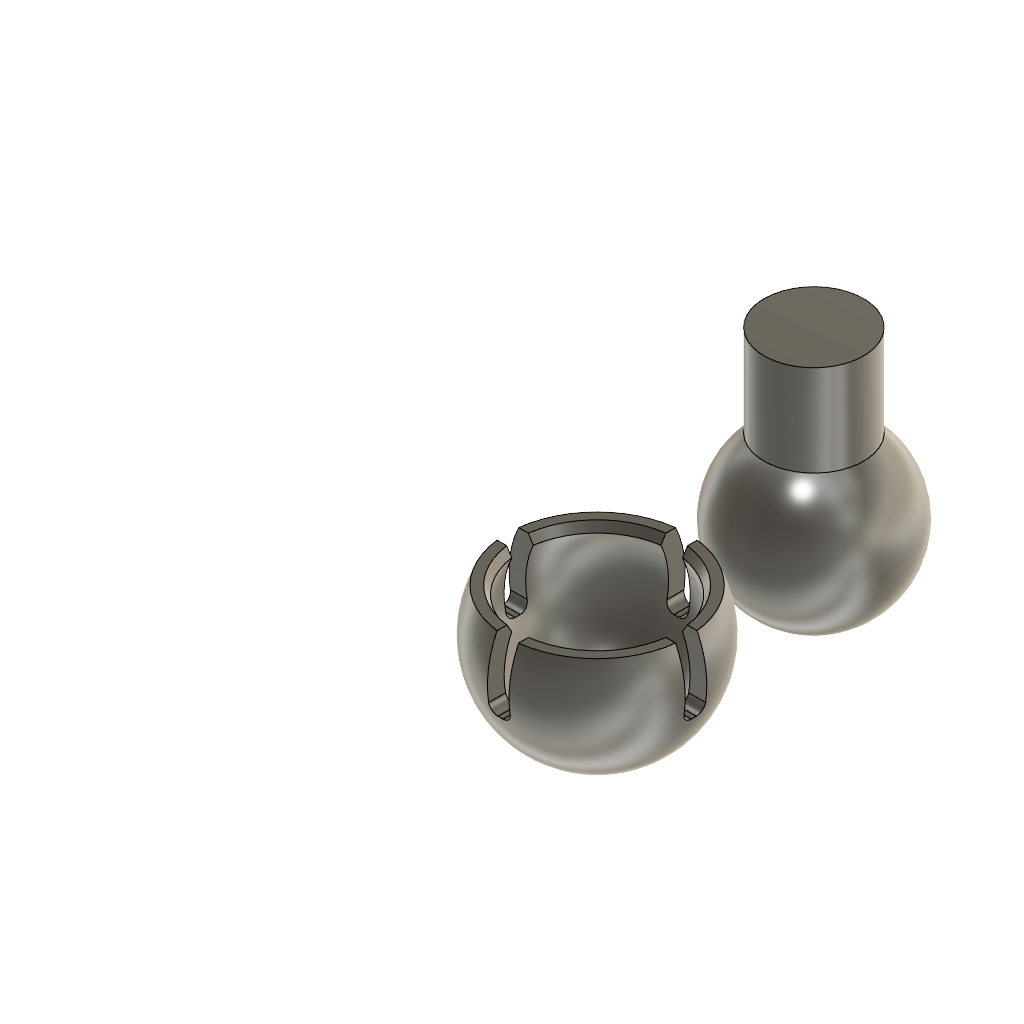
Bal&Socket (Autodesk Fusion 360 design; units mm, degrees)
Autodesk Fusion 360 part; units mm, degrees
sketch "Sketch2" plane through (0, 0, 0) normal (0, 1, 0) x (1, 0, 0)
  line L0 (0, -59.2722) -> (0, 62.6051)
  arc A0 (0, -50) -> (0, 50) centre (0, 0) ccw
  dimension "d5" = 100
  constraint coincident A0.centre origin
  constraint vertical L0
  constraint coincident L0 A0.end
  constraint coincident L0 A0.start
  constraint coincident A0.centre L0
  measures "d5" diameter of A0
revolve "Revolve1" add sketch "Sketch2" angle 360 about axis through (0, 0, 59.2722) along (0, 0, -1) makes body 1
ref_plane "WorkPlane1" through (0, 45, 0) normal (0, 1, 0) x (0, 0, 1)
sketch "Sketch4" plane through (0, 45, 0) normal (0, 1, 0) x (1, 0, 0)
  circle A0 centre (0, 0) radius 50
  circle A1 centre (0, 0) radius 30
  dimension "d9" = 60
  constraint concentric A0 A1
  measures "d9" diameter of A1
extrude "Extrude2" add sketch "Sketch4" along normal blind 55 separate body contours A1 makes body 2
copy_body "CopyPasteBodies1" bodies 1 makes body 3
move_body "Move1" bodies 3 to x (1, 0, 0) y (0, 1, 0) z (0, 0, 1) at (-128.8278, -193.9843, -63.6974)
move_body "Move2" bodies 2 to x (1, 0, 0) y (0, 0, 1) z (0, -1, 0) at (0, 0, 0)
move_face "OffsetFaces1" offset 10 1 faces at (-81.424, -182.1652, -74.3367) on bodies 3
move_body "Move3" bodies 1 2 to x (1, 0, 0) y (0, 1, 0) z (0, 0, 1) at (204.8691, 266.1175, 12.3114)
move_body "Move6" bodies 3 to x (1, 0, 0) y (0, 1, 0) z (0, 0, 1) at (185.6418, 249.1989, 118.0047)
sketch "Sketch6" plane through (0, 0, 0) normal (0, 1, 0) x (1, 0, 0)
ref_plane "WorkPlane2" through (0, 0, 80) normal (0, 0, 1) x (1, 0, 0)
split "Split1" by plane through (0, 0, 80) normal (0, 0, 1) bodies 3 makes body 4 at (101.0581, 47.4131, 94.0768)
copy_body "CopyPasteBodies3" bodies 1 makes body 5
move_body "Move7" bodies 5 to x (1, 0, 0) y (0, 1, 0) z (0, 0, 1) at (-89.9127, -41.461, -15.643)
move_body "Align1" bodies 5 to x (1, 0, 0) y (0, 1, 0) z (0, 0, 1) at (-58.1423, -169.4419, 57.639)
combine "Combine1" operation cut target body 3 tool bodies 5
sketch "Sketch7" plane through (0, 0, 0) normal (0, 1, 0) x (1, 0, 0)
  line L0 (50.3141, -80) -> (63.3141, -80)
  line L1 (63.3141, -80) -> (63.3141, -40)
  line L2 (63.3141, -40) -> (50.3141, -40)
  line L3 (50.3141, -40) -> (50.3141, -80)
  line L4 (56.8141, -80) -> (111.0348, -80)
  line L5 (2.5933, -80) -> (56.8141, -80)
  arc A0 (111.0348, -80) -> (2.5933, -80) centre (56.8141, -54.3074) ccw
  line L6 (-14.997, -80) -> (130.0763, -80)
  dimension "d18" = 40
  dimension "d19" = 13
  constraint horizontal L0
  constraint vertical L1
  constraint horizontal L2
  constraint vertical L3
  constraint parallel L4 L6
  constraint midpoint L0 L4.start
  measures "d18" distance of L0 L2
  measures "d19" distance of L1 L3
extrude "Extrude3" add sketch "Sketch7" along normal blind 130 and the other way blind 70 separate body contours L0 L1 L2 L3 L4 L5 L6 makes body 6
fillet "Fillet1" radius 5 2 edges at (50.3141, 30, 40) (63.3141, 30, 40) on bodies 6
combine "Combine2" operation cut target body 3 tool bodies 6
combine "Combine3" operation add target body 1 tool bodies 2
move_body "Align2" bodies 3 to x (1, 0, 0) y (0, 1, 0) z (0, 0, 1) at (148.055, 210.903, -41.996)
move_body "Move8" bodies 3 to x (1, 0, 0) y (0, 1, 0) z (0, 0, 1) at (-4.8817, -125.8159, 0)
chamfer "Chamfer2" distance 5.5 angle 45 2 edges at (157.0935, 140.3016, 38.004) (242.8814, 140.3016, 38.004) tangent chain off on bodies 3
sketch "Sketch9" plane through (0, 0, 0) normal (1, 0, 0) x (0, 1, 0)
  arc A0 (86.4718, 38.004) -> (81.3853, 3.004) centre (140.3016, 12.3114) ccw
  arc A1 (199.2178, 3.004) -> (194.1313, 38.004) centre (140.3016, 12.3114) ccw
  spline S0 degree 3 poles (199.2178, 3.004) (199.2176, 3.0028) (199.2174, 3.0016) (199.1185, 2.3754) (199.0159, 1.7077) (198.8335, 0.4769) (198.7538, -0.0861) (198.6942, -0.5315) (198.6351, -0.9738) (198.5881, -1.3584) (198.5382, -1.8693) (198.5353, -1.9955) (198.5514, -1.996) (198.5514, -1.996) (198.5514, -1.996) knots -0.379998 -0.379998 -0.379998 -0.379998 -0.379627 -0.379627 -0.189813 -0.189813 0 0 0 0.188468 0.188468 0.376936 0.376936 0.377335 0.377335 0.377335 0.377335
  line L0 (198.5514, -1.996) -> (198.5708, -1.996)
  line L1 (82.0324, -1.996) -> (82.0517, -1.996)
  spline S1 degree 3 poles (82.0517, -1.996) (82.0517, -1.996) (82.0517, -1.996) (82.0679, -1.9955) (82.065, -1.8693) (82.015, -1.3584) (81.968, -0.9738) (81.9089, -0.5315) (81.8493, -0.0861) (81.7696, 0.4769) (81.5872, 1.7077) (81.4846, 2.3754) (81.3857, 3.0016) (81.3855, 3.0028) (81.3853, 3.004) knots -0.377335 -0.377335 -0.377335 -0.377335 -0.376936 -0.376936 -0.188468 -0.188468 0 0 0 0.189813 0.189813 0.379627 0.379627 0.379998 0.379998 0.379998 0.379998
  line L2 (194.1313, 38.004) -> (86.4718, 38.004)
  arc A2 (82.0324, -1.996) -> (198.5708, -1.996) centre (140.3016, 12.3114) ccw
  line L3 (86.4718, 38.004) -> (194.1313, 38.004)
  line L4 (146.8016, -1.996) -> (133.8016, -1.996)
  line L5 (133.8016, -1.996) -> (133.8016, 38.004)
  line L6 (133.8016, 38.004) -> (146.8016, 38.004)
  line L7 (146.8016, 38.004) -> (146.8016, -1.996)
  line L8 (146.8016, -1.996) -> (133.8016, 38.004) construction
  line L9 (133.8016, -1.996) -> (146.8016, 38.004) construction
  point P0 (140.3016, 18.004)
  dimension "d30" = 13
  dimension "d31" = 40
  constraint horizontal L4
  constraint perpendicular L4 L5
  constraint parallel L4 L6
  constraint parallel L5 L7
  constraint coincident L8 P0
  constraint coincident L9 P0
  constraint midpoint L3 L6
  measures "d30" distance of L5.end L6.end
  measures "d31" distance of L4.end L5.end
extrude "Extrude4" add sketch "Sketch9" along normal blind 350 separate body contours L2 L3 L4 L5 L6 L7 makes body 7
fillet "Fillet2" radius 5 2 edges at (175, 133.8016, -1.996) (175, 146.8016, -1.996) on bodies 7
combine "Combine4" operation cut target body 3 tool bodies 7
hidden bodies 4
named bodies: "ball", "holder ball", "socket", "leftover", "ball (1)"
